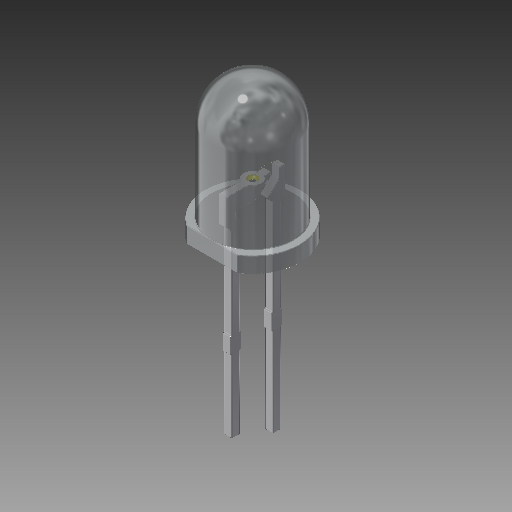
# Autodesk Inventor part: 5mm LED
Saved by Autodesk Inventor 2019 (Build 230136000, 136)
## iProperties
Created: 2015-03-31
Part Number: 5mm LED
Material: Glass
Document SubType Name: Modeling
Designer: Admin
Density: 2.18 g/cm^3
Appearance: Clear
Author: Admin
Autodesk Inventor part; units mm, degrees
ref_plane "YZ Plane" through (0, 0, 0) normal (1, 0, 0) x (0, 1, 0)
ref_plane "XZ Plane" through (0, 0, 0) normal (0, 1, 0) x (-1, 0, 0)
ref_plane "XY Plane" through (0, 0, 0) normal (0, 0, 1) x (1, 0, 0)
sketch "Sketch1" plane through (0, 0, 0) normal (1, 0, 0) x (0, 1, 0)
  line L0 (0, -1.8236) -> (0, 10.9413) projected
  line L1 (-3.6213, 0) -> (0.6036, 0) projected
  line L2 (0, 0) -> (-2.95, 0)
  line L3 (-2.95, 0) -> (-2.95, 1)
  line L4 (-2.95, 1) -> (0, 1)
  line L5 (0, 1) -> (0, 0)
  line L6 (0, 0) -> (-2.5, 0)
  line L7 (-2.5, 0) -> (-2.5, 6.1)
  line L8 (0, 8.6) -> (0, 8.6)
  line L9 (0, 8.6) -> (0, 0)
  arc A0 (0, 8.6) -> (-2.5, 6.1) centre (0, 6.1) ccw
  point P0 (-2.5, 8.6)
  dimension "d0" = 2.95
  dimension "d1" = 1
  dimension "d2" = 2.5
  dimension "d3" = 8.6
  dimension "d4" = 2.5
  constraints: 16 end point, 4 parallel, 4 point on line, 2 horizontal, 2 perpendicular, 2 point on circle, 2 tangent, 1 centre point
  measures "d0" distance of L3.end L4.end
  measures "d1" distance of L2.end L3.end
  measures "d2" distance of point (-2.5, 8.6) L8.end
  measures "d3" distance of L6.end point (-2.5, 8.6)
  measures "d4" radius of A0
revolve "Revolution1" add sketch "Sketch1" angle 360 about axis through (0, 0, -10) along (0, 0, 1)
sketch "Sketch2" plane through (0, 0, 0) normal (0, 0, 1) x (1, 0, 0)
  circle A0 centre (0, 0) radius 2.95 projected
  circle A1 centre (0, 0) radius 2.5 projected
  line L0 (-2.5, 1.566) -> (-2.5, -1.566)
  constraints: 2 end point, 2 point on circle, 1 tangent, 1 vertical
extrude "Extrusion1" cut sketch "Sketch2" along normal through all contours L0 A0 picked at (-2.5951, -0.846)
fillet "Fillet1" radius 0.05 2 edges at (1.7678, 1.7678, 1) (-1.7678, -1.7678, 1)
fillet "Fillet1" radius 0.05 7 edges at (-2.5, 0, 0) (2.95, 0, 0) (2.95, 0, 1) (-2.5, 1.566, 0.5) (-2.5, -1.566, 0.5) (-2.5, 0.783, 1) (-2.5, -0.783, 1)
sketch "Sketch3" plane through (0, 0, 0) normal (0, 1, 0) x (-1, 0, 0)
  line L0 (3.6136, 0) -> (-4.0439, 0) projected
  line L1 (1.52, 0) -> (1.02, 0)
  line L2 (1.02, 0) -> (1.02, -4.5)
  line L3 (1.02, -10) -> (1.52, -10)
  line L4 (1.52, -10) -> (1.52, -5.5)
  line L5 (0.945, -4.5) -> (1.02, -4.5)
  line L6 (1.595, -4.5) -> (1.595, -5.5)
  line L7 (1.595, -5.5) -> (1.52, -5.5)
  line L8 (0.945, -5.5) -> (0.945, -4.5)
  line L9 (1.52, -4.5) -> (1.52, 0)
  line L10 (1.02, -5.5) -> (1.02, -10)
  line L11 (1.52, -4.5) -> (1.595, -4.5)
  line L12 (1.02, -5.5) -> (0.945, -5.5)
  line L13 (0, -13.72) -> (0, 12.32) projected
  line L14 (1.02, 1.4631) -> (1.02, 0)
  line L15 (1.52, 0) -> (1.02, 0)
  line L16 (1.52, 0) -> (1.52, 1.1114)
  line L17 (1.52, 1.1114) -> (1.8629, 1.4543)
  line L18 (1.8629, 1.4543) -> (1.8629, 3.0716)
  line L19 (1.8629, 3.0716) -> (-1.02, 3.0716)
  line L20 (-1.02, 3.0716) -> (0, 2.0516)
  line L21 (0, 2.0516) -> (1.2656, 2.0516)
  line L22 (1.2656, 2.0516) -> (1.2656, 1.7087)
  line L23 (1.2656, 1.7087) -> (1.02, 1.4631)
  line L24 (-1.52, 0) -> (-1.52, 1.1837)
  line L25 (-1.52, 1.1837) -> (-1.7906, 1.4543)
  line L26 (-1.7906, 1.4543) -> (-1.7906, 3.0379)
  line L27 (-1.7906, 3.0379) -> (-1.7906, 3.0716)
  line L28 (-1.7906, 3.0716) -> (-1.4031, 3.0716)
  line L29 (-1.4031, 3.0716) -> (-1.4031, 2.4562)
  line L30 (-1.4031, 2.4562) -> (-0.753, 1.8061)
  line L31 (-0.753, 1.8061) -> (-0.753, 1.7087)
  line L32 (-0.753, 1.7087) -> (-1.02, 1.3936)
  line L33 (-1.02, 1.3936) -> (-1.02, 0)
  line L34 (-1.02, 0) -> (-1.52, 0)
  line L35 (-1.52, 0) -> (-1.52, -4.5)
  line L36 (-1.52, -10) -> (-1.02, -10)
  line L37 (-1.02, -10) -> (-1.02, -5.5)
  line L38 (-1.595, -4.5) -> (-1.52, -4.5)
  line L39 (-0.945, -4.5) -> (-0.945, -5.5)
  line L40 (-0.945, -5.5) -> (-1.02, -5.5)
  line L41 (-1.595, -5.5) -> (-1.595, -4.5)
  line L42 (-1.02, -4.5) -> (-1.02, 0)
  line L43 (-1.52, -5.5) -> (-1.52, -10)
  line L44 (-1.02, -4.5) -> (-0.945, -4.5)
  line L45 (-1.52, -5.5) -> (-1.595, -5.5)
  line L46 (-1.02, 0) -> (-1.52, 0)
  line L47 (-1.52, -10) -> (-1.02, -10)
  line L48 (-1.02, -10) -> (-1.02, -11)
  line L49 (-1.02, -11) -> (-1.52, -11)
  line L50 (-1.52, -11) -> (-1.52, -10)
  dimension "d10" = 0.5
  dimension "d11" = 10
  dimension "d13" = 1
  dimension "d14" = 0.075
  dimension "d15" = 0.075
  dimension "d16" = 0.65
  dimension "d17" = 4.5
  dimension "d26" = 135
  dimension "d27" = 45
  dimension "d28" = 135
  dimension "d29" = 0.5
  dimension "d30" = 10
  dimension "d31" = 1
  dimension "d32" = 0.075
  dimension "d33" = 0.075
  dimension "d34" = 0.65
  dimension "d35" = 2.54
  dimension "d43" = 1
  constraints: 98 end point, 29 parallel, 13 perpendicular, 12 collinear, 7 horizontal, 5 point on line, 2 vertical, 1 other
  measures "d10" distance of L3.end L3.start
  measures "d11" distance of L3.start L1.end
  measures "d13" distance of L6.start L6.end
  measures "d14" distance between parallel lines of L4 L6
  measures "d15" distance between parallel lines of L2 L8
  measures "d16" distance between parallel lines of L6 L8
  measures "d17" distance between parallel lines of L5 L0
  measures "d26" angle of L16 L17
  measures "d27" angle of L20 L19
  measures "d28" angle of L25 L24
  measures "d29" distance of L36.end L36.start
  measures "d30" distance of L36.start L24.start
  measures "d31" distance of L44.end L40.start
  measures "d32" distance between parallel lines of L37 L39
  measures "d33" distance between parallel lines of L35 L41
  measures "d34" distance between parallel lines of L39 L41
  measures "d35" distance between parallel lines of L10 L43
  measures "d43" distance of L47.end L48.end
extrude "Extrusion2" add sketch "Sketch3" along normal mid plane 0.5 separate body contours L9 L11 L6 L7 L4 L3 L10 L12 L8 L5 L2 L0 | L0 L14 L23 L22 L21 L13 L19 L18 L17 L16 | L20 L19 L13 | L42 L44 L39 L40 L37 L36 L43 L45 L41 L38 L35 L0 | L0 L24 L25 L26 L27 L28 L29 L30 L31 L32 L33 | L48 L49 L50 L36
fillet "Fillet2" radius 0.05 94 edges at (1.02, 0, -11) (1.02, 0.25, -8.25) (1.02, -0.25, -8.25) (1.52, 0, -11) (1.27, 0.25, -11) (1.27, -0.25, -11) (0.9825, 0.25, -5.5) (0.945, 0.25, -5) (0.9825, 0.25, -4.5) (1.02, 0.25, -1.5532) (0.8865, 0.25, 1.5511) (0.753, 0.25, 1.7574) (1.078, 0.25, 2.1312) (1.4031, 0.25, 2.7639) (1.5968, 0.25, 3.0716) (1.7906, 0.25, 2.2629) (1.6553, 0.25, 1.319) (1.52, 0.25, -1.6582) (1.5575, 0.25, -4.5) (1.595, 0.25, -5) (1.5575, 0.25, -5.5) (1.52, 0.25, -8.25) (0.945, 0, -5.5) (0.9825, -0.25, -5.5) (1.52, -0.25, -8.25) (0.945, 0, -4.5) (0.945, -0.25, -5) (0.9825, -0.25, -4.5) (1.02, -0.25, -1.5532) (0.753, 0, 1.7087) (0.8865, -0.25, 1.5511) (0.753, 0, 1.8061) (0.753, -0.25, 1.7574) (1.078, -0.25, 2.1312) (1.4031, 0, 3.0716) (1.4031, -0.25, 2.7639) (1.7906, 0, 3.0716) (1.5968, -0.25, 3.0716) (1.7906, 0, 1.4543) (1.7906, -0.25, 2.2629) (1.6553, -0.25, 1.319) (1.52, -0.25, -1.6582) (1.595, 0, -4.5) (1.5575, -0.25, -4.5) (1.595, 0, -5.5) (1.595, -0.25, -5) (1.5575, -0.25, -5.5) (-1.02, 0, 1.4631) (-1.02, 0.25, -1.5184) (-1.02, -0.25, -1.5184) (-1.1428, 0.25, 1.5859) (-1.1428, -0.25, 1.5859) (-0.9825, 0.25, -4.5) (-0.945, 0.25, -5) (-0.9825, 0.25, -5.5) (-1.02, 0.25, -7.75) (-1.27, 0.25, -10) (-1.52, 0.25, -7.75) (-1.5575, 0.25, -5.5) (-1.595, 0.25, -5) (-1.5575, 0.25, -4.5) (-1.52, 0.25, -1.6943) (-1.6914, 0.25, 1.2828) (-1.8629, 0.25, 2.2629) (-0.4214, 0.25, 3.0716) (0.51, 0.25, 2.5616) (-0.6328, 0.25, 2.0516) (-1.2656, 0.25, 1.8802) (-0.945, 0, -4.5) (-0.9825, -0.25, -4.5) (-1.2656, -0.25, 1.8802) (-0.945, 0, -5.5) (-0.945, -0.25, -5) (-0.9825, -0.25, -5.5) (-1.02, 0, -10) (-1.02, -0.25, -7.75) (-1.52, 0, -10) (-1.27, -0.25, -10) (-1.52, -0.25, -7.75) (-1.595, 0, -5.5) (-1.5575, -0.25, -5.5) (-1.595, 0, -4.5) (-1.595, -0.25, -5) (-1.5575, -0.25, -4.5) (-1.52, -0.25, -1.6943) (-1.8629, 0, 1.4543) (-1.6914, -0.25, 1.2828) (-1.8629, 0, 3.0716) (-1.8629, -0.25, 2.2629) (1.02, 0, 3.0716) (-0.4214, -0.25, 3.0716) (0, 0, 2.0516) (0.51, -0.25, 2.5616) (-0.6328, -0.25, 2.0516)
fillet "Fillet3" radius 0.05 42 edges at (1.02, 0, -5.5) (1.0346, -0.2354, -5.4854) (1.0346, 0.2354, -5.4854) (1.5054, -0.2354, -5.4854) (1.0346, -0.2354, -4.5146) (1.0346, -0.2354, 1.399) (1.5054, -0.2354, -4.5146) (1.5054, -0.2354, 1.1898) (1.4177, -0.2354, 2.4501) (1.5054, 0.2354, -5.4854) (1.0346, 0.2354, -4.5146) (1.0346, 0.2354, 1.399) (1.5054, 0.2354, -4.5146) (1.5054, 0.2354, 1.1898) (1.4177, 0.2354, 2.4501) (1.52, 0, -5.5) (1.02, 0, -4.5) (1.02, 0, 1.3936) (1.52, 0, -4.5) (1.52, 0, 1.1837) (1.4031, 0, 2.4562) (-1.02, 0, -4.5) (-1.0346, -0.2354, -4.5146) (-1.0346, 0.2354, -4.5146) (-1.2656, 0, 1.7087) (-1.2802, -0.2354, 1.7026) (-1.2802, -0.2354, 2.0663) (-1.0346, -0.2354, -5.4854) (-1.5054, -0.2354, -5.4854) (-1.5054, -0.2354, 1.1174) (-1.5054, -0.2354, -4.5146) (-1.2802, 0.2354, 1.7026) (-1.2802, 0.2354, 2.0663) (-1.0346, 0.2354, -5.4854) (-1.5054, 0.2354, -5.4854) (-1.5054, 0.2354, 1.1174) (-1.5054, 0.2354, -4.5146) (-1.2656, 0, 2.0516) (-1.02, 0, -5.5) (-1.52, 0, -5.5) (-1.52, 0, 1.1114) (-1.52, 0, -4.5)
sketch "Sketch4" plane through (0, 0, 0) normal (0, 1, 0) x (-1, 0, 0)
  line L0 (0, -13.72) -> (0, 12.32) projected
  line L1 (1.8129, 3.0716) -> (-0.8993, 3.0716) projected
  line L2 (-0.5445, 3.0716) -> (-0.1328, 2.6599)
  line L3 (-0.5445, 3.0716) -> (0.0378, 3.0716) construction
  line L4 (-0.1328, 2.6599) -> (0, 2.6599)
  arc A0 (-0.296, 3.0716) -> (0, 2.9465) centre (-0.0359, 3.2741) ccw
  line L5 (-0.5445, 3.0716) -> (-0.296, 3.0716)
  line L6 (0, 2.9465) -> (0, 2.6599)
  dimension "d40" = 45
  constraints: 10 end point, 4 point on line, 2 collinear, 2 point on circle, 1 centre point, 1 equal length, 1 horizontal, 1 perpendicular
  measures "d40" angle of L2 L3
revolve "Revolution2" add sketch "Sketch4" angle 360 about axis through (0, 0, -10) along (0, 0, 1) bodies 2 contours L4 L2 L1 A0 L0
sketch "Sketch5" plane through (0, 0, 0) normal (0, 1, 0) x (-1, 0, 0)
  arc A0 (-0.296, 3.0716) -> (0, 2.9465) centre (-0.0359, 3.2741) ccw projected
  line L0 (0, 2.9465) -> (0, 3.0716)
  line L1 (0, 3.0716) -> (-0.296, 3.0716)
  line L2 (0, -13.72) -> (0, 12.32) projected
  constraints: 4 end point, 1 perpendicular, 1 vertical
revolve "Revolution3" cut sketch "Sketch5" angle 360 about axis through (0, 0, -10) along (0, 0, 1) bodies 2
sketch "Sketch6" plane through (0, 0, 0) normal (0, 1, 0) x (-1, 0, 0)
  line L0 (-0.296, 3.0716) -> (0.296, 3.0716) projected
  arc A0 (-0.296, 3.0716) -> (-0.0359, 2.9445) centre (-0.0359, 3.2741) ccw projected
  arc A1 (0, 2.9731) -> (-0.1429, 2.9624) centre (0, 2.0152) ccw
  line L1 (0, -14.92) -> (0, 12.52) projected
  arc A2 (-0.1429, 2.9624) -> (0, 2.9465) centre (-0.0359, 3.2741) ccw
  line L2 (0, 2.9731) -> (0, 2.9465)
  constraints: 5 point on circle, 2 centre point, 2 end point, 1 collinear, 1 concentric, 1 line through centre
revolve "Revolution4" add sketch "Sketch6" angle 360 about axis through (0, 0, -10) along (0, 0, 1) separate body contours A1 L1 A2 A0
sketch "Sketch7" plane through (0, 0, 0) normal (0, 1, 0) x (-1, 0, 0)
  line L0 (-1.7406, 3.0716) -> (-1.4531, 3.0716) projected
  line L1 (-1.4531, 3.0716) -> (-1.7406, 3.0716) projected
  arc A0 (0.1429, 2.9624) -> (-0.1429, 2.9624) centre (0, 2.0152) ccw projected
  spline S0 degree 3 poles (-1.5968, 3.0716) (-1.4152, 3.4387) (-0.2883, 3.5777) (0, 2.9731) knots 0 0 0 0 1 1 1 1
  point P0 (-1.2649, 3.3137)
  point P1 (-0.5403, 3.3581)
  constraints: 1 midpoint, 1 point on circle, 4 other
sketch "Sketch8" plane through (1.4531, -0.2, 3.0716) normal (0, 0, 1) x (1, 0, 0)
  circle A0 centre (0.1438, 0.2) radius 0.0125
  dimension "d45" = 0.025
  constraints: 1 centre point, 1 coincident
  measures "d45" diameter of A0
sweep "Sweep1" add profiles "Sketch8" path "Sketch7" separate body path curves S0
equation "\"d15\" = d14"
equation "\"d33\" = d32"
body "Solid1"
body "Solid2"
body "Solid3"
body "Solid4"
